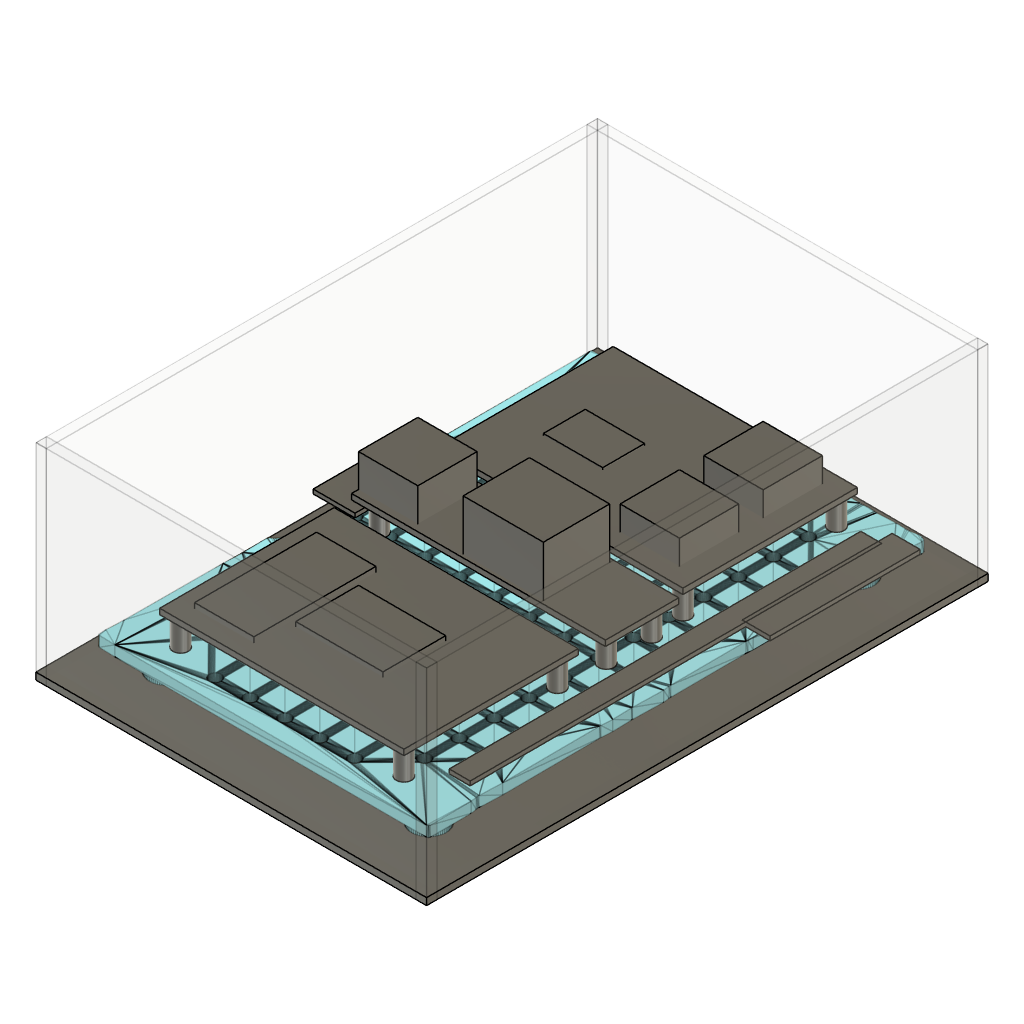
R1_PROVISIONAL_Assembly (Autodesk Fusion 360 design; units mm, degrees)
part number: 2026-11-12-00-33-55-556
part number: 2026-11-12-00-33-55-709
part number: 2026-11-12-00-33-55-834
part number: 2026-11-12-00-33-55-972
part number: 2026-11-12-00-33-56-028
part number: 2026-11-12-00-33-56-118
part number: 2026-11-12-00-33-56-195
part number: 2026-11-12-00-33-56-485
part number: 2026-11-12-00-33-56-584
Autodesk Fusion 360 part; units mm, degrees
sketch "Enclosure floor (provisional) footprint" plane through (0, 0, 0) normal (0, 0, 1) x (1, 0, 0) in component "PROVISIONAL Existing Box Envelope 112x161x59"
  line L0 (-8.5, -9) -> (103.5, -9)
  line L1 (103.5, -9) -> (103.5, 152)
  line L2 (103.5, 152) -> (-8.5, 152)
  line L3 (-8.5, 152) -> (-8.5, -9)
extrude "Extrude1" add sketch "Enclosure floor (provisional) footprint" along normal blind 2 makes body 1 in component "PROVISIONAL Existing Box Envelope 112x161x59"
sketch "LEFT wall footprint" plane through (0, 0, 0) normal (0, 0, 1) x (1, 0, 0) in component "PROVISIONAL Existing Box Envelope 112x161x59"
  line L0 (-8.5, -9) -> (-5.5, -9)
  line L1 (-5.5, -9) -> (-5.5, 152)
  line L2 (-5.5, 152) -> (-8.5, 152)
  line L3 (-8.5, 152) -> (-8.5, -9)
extrude "Extrude2" add sketch "LEFT wall footprint" along normal blind 59 separate body makes body 2 in component "PROVISIONAL Existing Box Envelope 112x161x59"
sketch "RIGHT wall footprint" plane through (0, 0, 0) normal (0, 0, 1) x (1, 0, 0) in component "PROVISIONAL Existing Box Envelope 112x161x59"
  line L0 (100.5, -9) -> (103.5, -9)
  line L1 (103.5, -9) -> (103.5, 152)
  line L2 (103.5, 152) -> (100.5, 152)
  line L3 (100.5, 152) -> (100.5, -9)
extrude "Extrude3" add sketch "RIGHT wall footprint" along normal blind 59 separate body makes body 3 in component "PROVISIONAL Existing Box Envelope 112x161x59"
sketch "LOWER wall footprint" plane through (0, 0, 0) normal (0, 0, 1) x (1, 0, 0) in component "PROVISIONAL Existing Box Envelope 112x161x59"
  line L0 (-8.5, -9) -> (103.5, -9)
  line L1 (103.5, -9) -> (103.5, -6)
  line L2 (103.5, -6) -> (-8.5, -6)
  line L3 (-8.5, -6) -> (-8.5, -9)
extrude "Extrude4" add sketch "LOWER wall footprint" along normal blind 59 separate body makes body 4 in component "PROVISIONAL Existing Box Envelope 112x161x59"
sketch "UPPER wall footprint" plane through (0, 0, 0) normal (0, 0, 1) x (1, 0, 0) in component "PROVISIONAL Existing Box Envelope 112x161x59"
  line L0 (-8.5, 149) -> (103.5, 149)
  line L1 (103.5, 149) -> (103.5, 152)
  line L2 (103.5, 152) -> (-8.5, 152)
  line L3 (-8.5, 152) -> (-8.5, 149)
extrude "Extrude5" add sketch "UPPER wall footprint" along normal blind 59 separate body makes body 5 in component "PROVISIONAL Existing Box Envelope 112x161x59"
other "Base Mesh Feature1" in component "APPROVED P4 plate - unchanged mesh 95.1599x142.652"
sketch "Perfboard A 70x50 footprint" plane through (0, 0, 0) normal (0, 0, 1) x (1, 0, 0) in component "Board A PROVISIONAL - ADC/pressure 70x50"
  line L0 (0, 0) -> (70, 0)
  line L1 (70, 0) -> (70, 50)
  line L2 (70, 50) -> (0, 50)
  line L3 (0, 50) -> (0, 0)
extrude "Extrude1'" add sketch "Perfboard A 70x50 footprint" along normal blind 1.6 separate body makes body 6 in component "Board A PROVISIONAL - ADC/pressure 70x50"
sketch "ADS1115 breakout placeholder footprint" plane through (0, 0, 0) normal (0, 0, 1) x (1, 0, 0) in component "Board A PROVISIONAL - ADC/pressure 70x50"
  line L0 (24, 15) -> (49, 15)
  line L1 (49, 15) -> (49, 33)
  line L2 (49, 33) -> (24, 33)
  line L3 (24, 33) -> (24, 15)
extrude "Extrude2'" add sketch "ADS1115 breakout placeholder footprint" along normal blind 2.8 separate body makes body 7 in component "Board A PROVISIONAL - ADC/pressure 70x50"
sketch "R1-R4 and C1-C2 placement envelope footprint" plane through (0, 0, 0) normal (0, 0, 1) x (1, 0, 0) in component "Board A PROVISIONAL - ADC/pressure 70x50"
  line L0 (5, 5) -> (22, 5)
  line L1 (22, 5) -> (22, 40)
  line L2 (22, 40) -> (5, 40)
  line L3 (5, 40) -> (5, 5)
extrude "Extrude3'" add sketch "R1-R4 and C1-C2 placement envelope footprint" along normal blind 3 separate body makes body 8 in component "Board A PROVISIONAL - ADC/pressure 70x50"
sketch "Perfboard B 70x50 footprint" plane through (0, 0, 0) normal (0, 0, 1) x (1, 0, 0) in component "Board B PROVISIONAL - field terminals 70x50"
  line L0 (0, 0) -> (70, 0)
  line L1 (70, 0) -> (70, 50)
  line L2 (70, 50) -> (0, 50)
  line L3 (0, 50) -> (0, 0)
extrude "Extrude1''" add sketch "Perfboard B 70x50 footprint" along normal blind 1.6 separate body makes body 9 in component "Board B PROVISIONAL - field terminals 70x50"
sketch "J1 PRESS 3-position +5V GND SIG footprint" plane through (0, 0, 0) normal (0, 0, 1) x (1, 0, 0) in component "Board B PROVISIONAL - field terminals 70x50"
  line L0 (47, 5) -> (64, 5)
  line L1 (64, 5) -> (64, 22)
  line L2 (64, 22) -> (47, 22)
  line L3 (47, 22) -> (47, 5)
extrude "Extrude2''" add sketch "J1 PRESS 3-position +5V GND SIG footprint" along normal blind 8.5 separate body makes body 10 in component "Board B PROVISIONAL - field terminals 70x50"
sketch "J2 TEMP 3-position +3V3 DATA GND footprint" plane through (0, 0, 0) normal (0, 0, 1) x (1, 0, 0) in component "Board B PROVISIONAL - field terminals 70x50"
  line L0 (47, 29) -> (64, 29)
  line L1 (64, 29) -> (64, 46)
  line L2 (64, 46) -> (47, 46)
  line L3 (47, 46) -> (47, 29)
extrude "Extrude3''" add sketch "J2 TEMP 3-position +3V3 DATA GND footprint" along normal blind 8.5 separate body makes body 11 in component "Board B PROVISIONAL - field terminals 70x50"
sketch "R5 pullup envelope footprint" plane through (0, 0, 0) normal (0, 0, 1) x (1, 0, 0) in component "Board B PROVISIONAL - field terminals 70x50"
  line L0 (12, 18) -> (29, 18)
  line L1 (29, 18) -> (29, 30)
  line L2 (29, 30) -> (12, 30)
  line L3 (12, 30) -> (12, 18)
extrude "Extrude4'" add sketch "R5 pullup envelope footprint" along normal blind 2 separate body makes body 12 in component "Board B PROVISIONAL - field terminals 70x50"
sketch "Waveshare PCB 72.8x21 footprint" plane through (0, 0, 0) normal (0, 0, 1) x (1, 0, 0) in component "Waveshare ESP32-S3-ETH PROVISIONAL 72.8x21"
  line L0 (0, 0) -> (72.8, 0)
  line L1 (72.8, 0) -> (72.8, 21)
  line L2 (72.8, 21) -> (0, 21)
  line L3 (0, 21) -> (0, 0)
extrude "Extrude1'''" add sketch "Waveshare PCB 72.8x21 footprint" along normal blind 1.6 separate body makes body 13 in component "Waveshare ESP32-S3-ETH PROVISIONAL 72.8x21"
sketch "RJ45 and magnetics envelope footprint" plane through (0, 0, 0) normal (0, 0, 1) x (1, 0, 0) in component "Waveshare ESP32-S3-ETH PROVISIONAL 72.8x21"
  line L0 (0, 2) -> (17, 2)
  line L1 (17, 2) -> (17, 19)
  line L2 (17, 19) -> (0, 19)
  line L3 (0, 19) -> (0, 2)
extrude "Extrude2'''" add sketch "RJ45 and magnetics envelope footprint" along normal blind 11 separate body makes body 14 in component "Waveshare ESP32-S3-ETH PROVISIONAL 72.8x21"
sketch "PoE expansion module envelope footprint" plane through (0, 0, 0) normal (0, 0, 1) x (1, 0, 0) in component "Waveshare ESP32-S3-ETH PROVISIONAL 72.8x21"
  line L0 (31, 1) -> (54, 1)
  line L1 (54, 1) -> (54, 20)
  line L2 (54, 20) -> (31, 20)
  line L3 (31, 20) -> (31, 1)
extrude "Extrude3'''" add sketch "PoE expansion module envelope footprint" along normal blind 16 separate body makes body 15 in component "Waveshare ESP32-S3-ETH PROVISIONAL 72.8x21"
sketch "Sketch1" plane through (0, 0, 0) normal (0, 0, 1) x (1, 0, 0) in component "PROVISIONAL removable support spacers"
  circle A0 centre (15, 9) radius 2.2
extrude "Extrude1''''" add sketch "Sketch1" along normal blind 8 separate body makes body 16 in component "PROVISIONAL removable support spacers"
sketch "Sketch2" plane through (0, 0, 0) normal (0, 0, 1) x (1, 0, 0) in component "PROVISIONAL removable support spacers"
  circle A0 centre (79, 9) radius 2.2
extrude "Extrude2''''" add sketch "Sketch2" along normal blind 8 separate body makes body 17 in component "PROVISIONAL removable support spacers"
sketch "Sketch3" plane through (0, 0, 0) normal (0, 0, 1) x (1, 0, 0) in component "PROVISIONAL removable support spacers"
  circle A0 centre (15, 53) radius 2.2
extrude "Extrude3''''" add sketch "Sketch3" along normal blind 8 separate body makes body 18 in component "PROVISIONAL removable support spacers"
sketch "Sketch4" plane through (0, 0, 0) normal (0, 0, 1) x (1, 0, 0) in component "PROVISIONAL removable support spacers"
  circle A0 centre (79, 53) radius 2.2
extrude "Extrude4''" add sketch "Sketch4" along normal blind 8 separate body makes body 19 in component "PROVISIONAL removable support spacers"
sketch "Sketch5" plane through (0, 0, 0) normal (0, 0, 1) x (1, 0, 0) in component "PROVISIONAL removable support spacers"
  circle A0 centre (15, 89) radius 2.2
extrude "Extrude5'" add sketch "Sketch5" along normal blind 8 separate body makes body 20 in component "PROVISIONAL removable support spacers"
sketch "Sketch6" plane through (0, 0, 0) normal (0, 0, 1) x (1, 0, 0) in component "PROVISIONAL removable support spacers"
  circle A0 centre (79, 89) radius 2.2
extrude "Extrude6" add sketch "Sketch6" along normal blind 8 separate body makes body 21 in component "PROVISIONAL removable support spacers"
sketch "Sketch7" plane through (0, 0, 0) normal (0, 0, 1) x (1, 0, 0) in component "PROVISIONAL removable support spacers"
  circle A0 centre (15, 133) radius 2.2
extrude "Extrude7" add sketch "Sketch7" along normal blind 8 separate body makes body 22 in component "PROVISIONAL removable support spacers"
sketch "Sketch8" plane through (0, 0, 0) normal (0, 0, 1) x (1, 0, 0) in component "PROVISIONAL removable support spacers"
  circle A0 centre (79, 133) radius 2.2
extrude "Extrude8" add sketch "Sketch8" along normal blind 8 separate body makes body 23 in component "PROVISIONAL removable support spacers"
sketch "Sketch9" plane through (0, 0, 0) normal (0, 0, 1) x (1, 0, 0) in component "PROVISIONAL removable support spacers"
  circle A0 centre (15, 66) radius 2.2
extrude "Extrude9" add sketch "Sketch9" along normal blind 8 separate body makes body 24 in component "PROVISIONAL removable support spacers"
sketch "Sketch10" plane through (0, 0, 0) normal (0, 0, 1) x (1, 0, 0) in component "PROVISIONAL removable support spacers"
  circle A0 centre (80, 66) radius 2.2
extrude "Extrude10" add sketch "Sketch10" along normal blind 8 separate body makes body 25 in component "PROVISIONAL removable support spacers"
sketch "Sketch11" plane through (0, 0, 0) normal (0, 0, 1) x (1, 0, 0) in component "PROVISIONAL removable support spacers"
  circle A0 centre (15, 79) radius 2.2
extrude "Extrude11" add sketch "Sketch11" along normal blind 8 separate body makes body 26 in component "PROVISIONAL removable support spacers"
sketch "Sketch12" plane through (0, 0, 0) normal (0, 0, 1) x (1, 0, 0) in component "PROVISIONAL removable support spacers"
  circle A0 centre (80, 79) radius 2.2
extrude "Extrude12" add sketch "Sketch12" along normal blind 8 separate body makes body 27 in component "PROVISIONAL removable support spacers"
sketch "Harness tie channel RIGHT footprint" plane through (0, 0, 0) normal (0, 0, 1) x (1, 0, 0) in component "Cable management concepts - not actual wires"
  line L0 (86, 15) -> (92, 15)
  line L1 (92, 15) -> (92, 133)
  line L2 (92, 133) -> (86, 133)
  line L3 (86, 133) -> (86, 15)
extrude "Extrude1'''''" add sketch "Harness tie channel RIGHT footprint" along normal blind 1.2 separate body makes body 28 in component "Cable management concepts - not actual wires"
sketch "RJ45 cable entry service envelope LEFT footprint" plane through (0, 0, 0) normal (0, 0, 1) x (1, 0, 0) in component "Cable management concepts - not actual wires"
  line L0 (-3, 65) -> (9, 65)
  line L1 (9, 65) -> (9, 82)
  line L2 (9, 82) -> (-3, 82)
  line L3 (-3, 82) -> (-3, 65)
extrude "Extrude2'''''" add sketch "RJ45 cable entry service envelope LEFT footprint" along normal blind 1.2 separate body makes body 29 in component "Cable management concepts - not actual wires"
sketch "Pressure and temp cable entry service envelope RIGHT footprint" plane through (0, 0, 0) normal (0, 0, 1) x (1, 0, 0) in component "Cable management concepts - not actual wires"
  line L0 (91, 94) -> (99, 94)
  line L1 (99, 94) -> (99, 137)
  line L2 (99, 137) -> (91, 137)
  line L3 (91, 137) -> (91, 94)
extrude "Extrude3'''''" add sketch "Pressure and temp cable entry service envelope RIGHT footprint" along normal blind 1.2 separate body makes body 30 in component "Cable management concepts - not actual wires"
sketch "Gasketed cover outline PROVISIONAL footprint" plane through (0, 0, 0) normal (0, 0, 1) x (1, 0, 0) in component "REMOVABLE LID - hidden for service view"
  line L0 (-8.5, -9) -> (103.5, -9)
  line L1 (103.5, -9) -> (103.5, 152)
  line L2 (103.5, 152) -> (-8.5, 152)
  line L3 (-8.5, 152) -> (-8.5, -9)
extrude "Extrude1''''''" add sketch "Gasketed cover outline PROVISIONAL footprint" along normal blind 3 separate body makes body 31 in component "REMOVABLE LID - hidden for service view"
component "PROVISIONAL Existing Box Envelope 112x161x59" placed x (1, 0, 0) y (0, 1, 0) z (0, 0, 1) at (0, 0, 0)
component "APPROVED P4 plate - unchanged mesh 95.1599x142.652" placed x (1, 0, 0) y (0, -1, 0) z (0, 0, -1) at (0, 142.652, 11)
component "Board A PROVISIONAL - ADC/pressure 70x50" placed x (1, 0, 0) y (0, 1, 0) z (0, 0, 1) at (12, 6, 19)
component "Board B PROVISIONAL - field terminals 70x50" placed x (1, 0, 0) y (0, 1, 0) z (0, 0, 1) at (12, 86, 19)
component "Waveshare ESP32-S3-ETH PROVISIONAL 72.8x21" placed x (1, 0, 0) y (0, 1, 0) z (0, 0, 1) at (11, 62, 19)
component "PROVISIONAL removable support spacers" placed x (1, 0, 0) y (0, 1, 0) z (0, 0, 1) at (0, 0, 11)
component "Cable management concepts - not actual wires" placed x (1, 0, 0) y (0, 1, 0) z (0, 0, 1) at (0, 0, 12)
component "REMOVABLE LID - hidden for service view" placed x (1, 0, 0) y (0, 1, 0) z (0, 0, 1) at (0, 0, 59)
named bodies: "Enclosure floor (provisional)", "LEFT wall", "RIGHT wall", "LOWER wall", "UPPER wall", "Perfboard A 70x50", "ADS1115 breakout placeholder", "R1-R4 and C1-C2 placement envelope", "Perfboard B 70x50", "J1 PRESS 3-position +5V GND SIG", "J2 TEMP 3-position +3V3 DATA GND", "R5 pullup envelope", "Waveshare PCB 72.8x21", "RJ45 and magnetics envelope", "PoE expansion module envelope", "A standoff mock 1", "A standoff mock 2", "A standoff mock 3", "A standoff mock 4", "B standoff mock 1", "B standoff mock 2", "B standoff mock 3", "B standoff mock 4", "ETH standoff mock 1", "ETH standoff mock 2", "ETH standoff mock 3", "ETH standoff mock 4", "Harness tie channel RIGHT", "RJ45 cable entry service envelope LEFT", "Pressure and temp cable entry service envelope RIGHT", "Gasketed cover outline PROVISIONAL"
